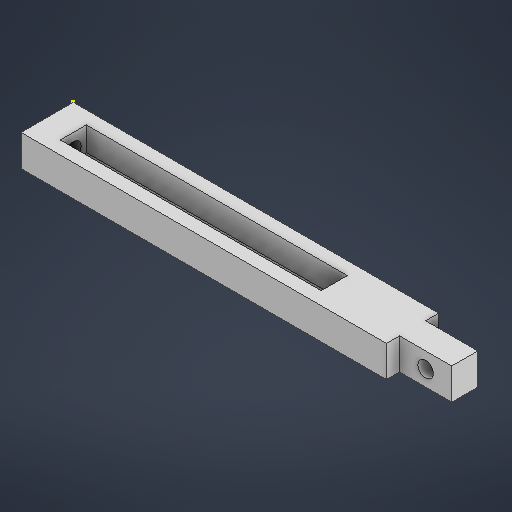
# Autodesk Inventor part: Part1
Saved by Autodesk Inventor 2027.2 (Build 312334000, 334)
## iProperties
Created: 2026-11-21
Part Number: Part1
Material: Generic
Document SubType Name: Modeling
Designer: junha
Density: 1 g/cm^3
Appearance: Default
Author: junha
Autodesk Inventor part; units mm, degrees
ref_plane "YZ Plane" through (0, 0, 0) normal (1, 0, 0) x (0, 1, 0)
ref_plane "XZ Plane" through (0, 0, 0) normal (0, 1, 0) x (-1, 0, 0)
ref_plane "XY Plane" through (0, 0, 0) normal (0, 0, 1) x (1, 0, 0)
sketch "Sketch1" plane through (0, 0, 0) normal (0, 0, 1) x (1, 0, 0)
  line L0 (0, 0) -> (80, 0)
  line L1 (80, 0) -> (80, 6)
  line L2 (80, 6) -> (0, 6)
  line L3 (0, 6) -> (0, 0)
  dimension "d0" = 80
  dimension "d1" = 6
  constraints: 8 end point, 2 horizontal, 1 perpendicular, 1 vertical
  measures "d0" distance of L0.start L0.end
  measures "d1" distance of L0.end L1.end
extrude "Extrusion1" add sketch "Sketch1" along normal blind 10
sketch "Sketch2" plane through (80, 0, 0) normal (1, 0, 0) x (0, 0, -1)
  line L0 (-10, 0) -> (-10, 6) projected
  line L1 (0, 0) -> (-10, 0) projected
  line L2 (-10, 6) -> (-7.5, 6)
  line L3 (-7.5, 6) -> (-7.5, 0)
  line L4 (-7.5, 0) -> (-10, 0)
  line L5 (-10, 0) -> (-10, 6)
  line L6 (0, 0) -> (0, 6) projected
  line L7 (0, 6) -> (-2.5, 6)
  line L8 (-2.5, 6) -> (-2.5, 0)
  line L9 (-2.5, 0) -> (0, 0)
  line L10 (0, 0) -> (0, 6)
  dimension "d4" = 2.5
  dimension "d5" = 2.5
  constraints: 16 end point, 4 parallel, 2 horizontal, 2 perpendicular, 2 point on line
  measures "d4" distance of L3.end L4.end
  measures "d5" distance of L9.end L8.end
extrude "Extrusion2" cut sketch "Sketch2" against normal blind 10
sketch "Sketch3" plane through (80, 0, 7.5) normal (0, 0, 1) x (1, 0, 0)
  line L0 (-10, 6) -> (-10, 0) projected
  line L1 (0, 0) -> (0, 6) projected
  line L2 (0, 6) -> (-10, 6) projected
  line L3 (-10, 0) -> (0, 0) projected
  circle A0 centre (-5, 3) radius 1.5
  point P0 (-80, 0)
  dimension "d8" = 3
  constraints: 1 centre point
  measures "d8" diameter of A0
extrude "Extrusion3" cut sketch "Sketch3" against normal blind 10 contours A0
sketch "Sketch4" plane through (0, 0, 0) normal (-1, 0, 0) x (0, 0, 1)
  line L0 (0, 6) -> (0, 0) projected
  line L1 (10, 6) -> (10, 0) projected
  line L2 (0, 6) -> (10, 6) projected
  line L3 (0, 0) -> (10, 0) projected
  circle A0 centre (5, 3) radius 1.5
  dimension "d11" = 3
  constraints: 1 centre point
  measures "d11" diameter of A0
extrude "Extrusion4" cut sketch "Sketch4" against normal blind 19 contours A0
sketch "Sketch5" plane through (0, 6, 10) normal (0, 1, 0) x (1, 0, 0)
  point P0 (0, 10)
sketch "Sketch6" plane through (0, 6, 10) normal (0, 1, 0) x (1, 0, 0)
  line L0 (70, 10) -> (0, 10) projected
  line L1 (70, 0) -> (0, 0) projected
  line L2 (5, 2.5) -> (55, 2.5)
  line L3 (55, 2.5) -> (55, 7.5)
  line L4 (55, 7.5) -> (5, 7.5)
  line L5 (5, 7.5) -> (5, 2.5)
  constraints: 8 end point, 2 parallel, 1 horizontal, 1 perpendicular
extrude "Extrusion5" cut sketch "Sketch6" against normal blind 4.6
body "Solid1"
